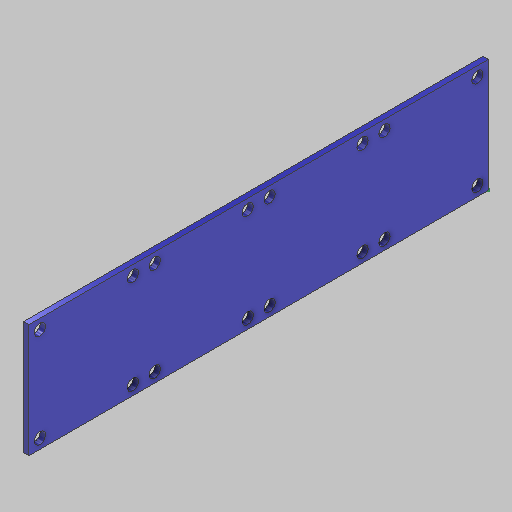
# Autodesk Inventor part: PCB_MATRIZ
Saved by Autodesk Inventor 2027 (Build 310192000, 192)
## iProperties
Created: 2026-11-23
Part Number: PCB_MATRIZ
Material: Genérico
Document SubType Name: Modeling
Designer: Alexander
Density: 1 g/cm^3
Appearance: Valor por defecto
Author: Alexander
Autodesk Inventor part; units mm, degrees
ref_plane "YZ Plane" through (0, 0, 0) normal (1, 0, 0) x (0, 1, 0)
ref_plane "XZ Plane" through (0, 0, 0) normal (0, 1, 0) x (-1, 0, 0)
ref_plane "XY Plane" through (0, 0, 0) normal (0, 0, 1) x (1, 0, 0)
sketch "Boceto1" plane through (0, 0, 0) normal (1, 0, 0) x (0, 1, 0)
  line L0 (0, 129.5) -> (0, 0)
  line L1 (32, 0) -> (32, 129.5)
  line L2 (0, 0) -> (0, 129.5)
  line L3 (0, 129.5) -> (32, 129.5)
  line L4 (32, 129.5) -> (32, 0)
  line L5 (32, 0) -> (0, 0)
  circle A0 centre (2.75, 126.4125) radius 1.6
  circle A1 centre (2.75, 126.4125) radius 1.6
  circle A2 centre (29.25, 126.4125) radius 1.6
  circle A3 centre (29.25, 126.4125) radius 1.6
  circle A4 centre (2.75, 100.2125) radius 1.6
  circle A5 centre (2.75, 100.2125) radius 1.6
  circle A6 centre (29.25, 100.2125) radius 1.6
  circle A7 centre (29.25, 94.0375) radius 1.6
  circle A8 centre (29.25, 94.0375) radius 1.6
  circle A9 centre (2.75, 94.0375) radius 1.6
  circle A10 centre (29.25, 67.8375) radius 1.6
  circle A11 centre (29.25, 67.8375) radius 1.6
  circle A12 centre (2.75, 67.8375) radius 1.6
  circle A13 centre (29.25, 61.6625) radius 1.6
  circle A14 centre (29.25, 61.6625) radius 1.6
  circle A15 centre (2.75, 61.6625) radius 1.6
  circle A16 centre (2.75, 61.6625) radius 1.6
  circle A17 centre (2.75, 35.4625) radius 1.6
  circle A18 centre (2.75, 35.4625) radius 1.6
  circle A19 centre (2.75, 29.2875) radius 1.6
  circle A20 centre (2.75, 29.2875) radius 1.6
  circle A21 centre (29.25, 29.2875) radius 1.6
  circle A22 centre (29.25, 29.2875) radius 1.6
  circle A23 centre (29.25, 35.4625) radius 1.6
  circle A24 centre (29.25, 35.4625) radius 1.6
  circle A25 centre (2.75, 3.0875) radius 1.6
  circle A26 centre (2.75, 3.0875) radius 1.6
  circle A27 centre (29.25, 3.0875) radius 1.6
  circle A28 centre (29.25, 3.0875) radius 1.6
  line L6 (0, 0) -> (32, 0)
  line L7 (32, 0) -> (32, 129.5)
  line L8 (32, 129.5) -> (0, 129.5)
  line L9 (0, 129.5) -> (0, 0)
  line L10 (0, 0) -> (32, 0)
  point P0 (0, 0)
  constraints: 29 centre point, 22 end point, 13 coincident, 4 parallel, 2 perpendicular
extrude "Extrusión1" add sketch "Boceto1" along normal blind 1.5
sketch "Boceto2" plane through (1.5, 0, 0) normal (1, 0, 0) x (0, 0, -1)
  point P0 (0, 0)
